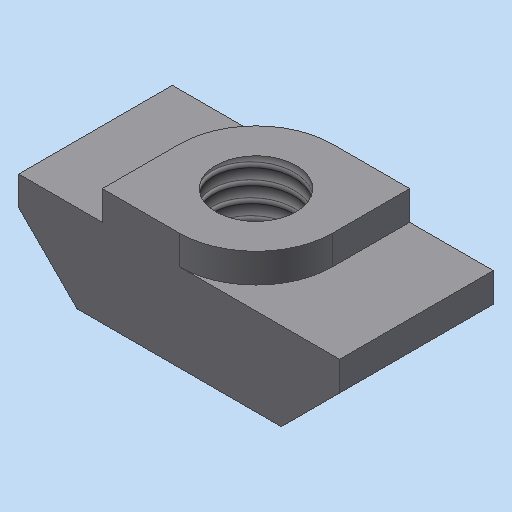
# Autodesk Inventor part: 3842501752_050515_001
Saved by Autodesk Inventor 2023.3 (Build 273359000, 359)
## iProperties
Shininess: 64.0
Length Units: 11269
Angle Units: 11279
Time Units: 11290
Mass Units: 11283
Length Display Precision: 3
Angle Display Precision: 2
Compacted: True
Part Number: 3842501752_050515_001
Document SubType Name: Modeling
Created: 2005-05-15
Material: xStahl_AnP_Dummymaterial
Manufacturer: Standard
Standards Organization: Custom
Description: =<RBPARTNOTITLE2>
Vendor: Bosch Rexroth
Density: 7.85 g/cm^3
Appearance: Vorgabe(1)
DOC_ID: 5 F45 3842501752_050515_001
GAIN_REFID: 20__3842501752_050515_001:DFF31
Control State: 0
Master: False
Checked Out: False
Ausgabe: 00
Blattnr: 000
Fläche: 0,000 mm^2
Masse: 0,000 kg
Volumen: 0,000 mm^3
DEF_STKID: T20942
Bezeichnung1: Hammermutter M5 Nut 8
RBPARTMADEOF: 3842501752  (1PE = 1 Stck)
RBDRAWINGMISSINGSPEC: --
AnP_Kategorie: 2
RBPARTNOTITLE2: Hammermutter M5 Nut 8
RBPARTNOTITLE1: T-nut, 6mm slot
Density: 0.0
Volumn: 0.0
Area: 0.0
PropertySet Name: Model Information
Keywords: =<RBPARTMADEOF>
Comments: =<RBSURFACE2>
Revision Number: 01
Autodesk Inventor part; units mm, degrees
ref_plane "YZ Plane" through (0, 0, 0) normal (1, 0, 0) x (0, 1, 0)
ref_plane "XZ Plane" through (0, 0, 0) normal (0, 1, 0) x (-1, 0, 0)
ref_plane "XY Plane" through (0, 0, 0) normal (0, 0, 1) x (1, 0, 0)
sketch "Skizze1" plane through (0, 0, 0) normal (0, 0, 1) x (1, 0, 0)
  line L0 (-8.25, 3.95) -> (8.25, 3.95)
  line L1 (8.25, 3.95) -> (8.25, -3.95)
  line L2 (8.25, -3.95) -> (-8.25, -3.95)
  line L3 (-8.25, -3.95) -> (-8.25, 3.95)
  point P0 (0, 0)
  dimension "d0" = 3.95
  dimension "d1" = 3.95
  dimension "d2" = 8.25
  dimension "d3" = 8.25
  constraints: 8 end point, 2 parallel, 1 horizontal, 1 perpendicular
  measures "d0" distance from line of L0 point (0, 0)
  measures "d1" distance from line of L2 point (0, 0)
  measures "d2" distance from line of L3 point (0, 0)
  measures "d3" distance from line of L1 point (0, 0)
extrude "Extrusion1" add sketch "Skizze1" along normal blind 6
sketch "Skizze2" plane through (0, 0, 6) normal (0, 0, 1) x (1, 0, 0)
  point P0 (0, 0)
  point P1 (0, 0)
  constraints: 1 coincident
hole "Bohrung1" at (0, 0, 6) direction (0, 0, -1) diameter 4.134 end through all thread size "M5x0.8" class "6H" standard "ISO Metrisches Profil"
sketch "Skizze3" plane through (0, 0, 6) normal (0, 0, 1) x (1, 0, 0)
  line L0 (-3.95, 0) -> (-3.95, -3.95)
  line L1 (0, -3.95) -> (-3.95, -3.95)
  line L2 (0, 3.95) -> (3.95, 3.95)
  line L3 (3.95, 3.95) -> (3.95, 0)
  arc A0 (0, -3.95) -> (3.95, 0) centre (0, 0) ccw
  arc A1 (0, 3.95) -> (-3.95, 0) centre (0, 0) ccw
  line L4 (-8.25, 3.95) -> (8.25, 3.95) projected
  line L5 (8.25, -3.95) -> (-8.25, -3.95) projected
  circle A2 centre (0, 0) radius 10
  dimension "d13" = 20
  constraints: 8 end point, 4 point on circle, 4 tangent, 3 centre point, 2 coincident, 2 collinear, 2 perpendicular, 1 parallel
  measures "d13" diameter of A2
extrude "Extrusion2" cut sketch "Skizze3" against normal blind 1.5
chamfer "Fase1" distance 3 angle 45 2 edges at (-8.25, 0, 0) (8.25, 0, 0)
